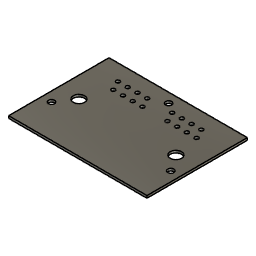
rj45-footprint v1 (Autodesk Fusion 360 design; units mm, degrees)
Autodesk Fusion 360 part; units mm, degrees
sketch "Skizze1" plane through (0, 0, 0) normal (0, 0, 1) x (1, 0, 0)
  circle A0 centre (16.27, 7.5) radius 0.5
  circle A1 centre (18.81, 7.5) radius 0.5
  circle A2 centre (21.35, 7.5) radius 0.5
  circle A3 centre (23.89, 7.5) radius 0.5
  circle A4 centre (17.54, 5) radius 0.5
  circle A5 centre (20.08, 5) radius 0.5
  circle A6 centre (22.62, 5) radius 0.5
  circle A7 centre (25.16, 5) radius 0.5
  circle A8 centre (31.66, 5) radius 0.5
  circle A9 centre (36.74, 5) radius 0.5
  circle A10 centre (35.47, 7.5) radius 0.5
  circle A11 centre (34.2, 5) radius 0.5
  circle A12 centre (39.28, 5) radius 0.5
  circle A13 centre (38.01, 7.5) radius 0.5
  circle A14 centre (32.93, 7.5) radius 0.5
  circle A15 centre (30.39, 7.5) radius 0.5
  circle A16 centre (15.125, -1.55) radius 1.5
  circle A17 centre (40.425, -1.55) radius 1.5
  circle A18 centre (12.225, -5.8) radius 0.8
  circle A19 centre (43.325, -5.8) radius 0.8
  circle A20 centre (27.775, 9.2) radius 0.8
  line L0 (27.775, 9.2) -> (27.775, -15) construction
  line L1 (16.27, 7.5) -> (39.28, 7.5) construction
  line L2 (39.28, 7.5) -> (39.28, 5) construction
  line L3 (39.28, 5) -> (16.27, 5) construction
  line L4 (16.27, 5) -> (16.27, 7.5) construction
  line L5 (12.225, 9.2) -> (43.325, 9.2)
  line L6 (43.325, 9.2) -> (43.325, -12)
  line L7 (43.325, -12) -> (12.225, -12)
  line L8 (12.225, -12) -> (12.225, 9.2)
  line L9 (45.825, -14.5) -> (9.725, -14.5)
  line L10 (9.725, -14.5) -> (9.725, 11.7)
  line L11 (9.725, 11.7) -> (45.825, 11.7)
  line L12 (45.825, 11.7) -> (45.825, -14.5)
  dimension "d1" = 1
  dimension "d2" = 2.54
  dimension "d3" = 2.54
  dimension "d4" = 2.54
  dimension "d5" = 2.54
  dimension "d6" = 2.54
  dimension "d7" = 2.54
  dimension "d9" = 2.5
  dimension "d10" = 1
  dimension "d11" = 2.54
  dimension "d12" = 2.54
  dimension "d13" = 2.54
  dimension "d14" = 2.54
  dimension "d15" = 2.54
  dimension "d16" = 2.54
  dimension "d18" = 2.5
  dimension "d19" = 6.5
  dimension "d20" = 1.6
  dimension "d21" = 3
  dimension "d22" = 31.1
  dimension "d23" = 25.3
  dimension "d24" = 2.9
  dimension "d25" = 1.27
  dimension "d26" = 1.27
  dimension "d27" = 15
  dimension "d29" = 4.25
  dimension "d30" = 6.55
  dimension "d31" = 21.2
  dimension "d32" = -2.5
  constraint equal A0 A1
  constraint equal A1 A2
  constraint equal A2 A3
  constraint equal A4 A5
  constraint equal A0 A4
  constraint equal A5 A6
  constraint equal A6 A7
  constraint horizontal A0.centre A1.centre
  constraint horizontal A1.centre A2.centre
  constraint horizontal A2.centre A3.centre
  constraint horizontal A4.centre A5.centre
  constraint horizontal A5.centre A6.centre
  constraint horizontal A6.centre A7.centre
  constraint equal A14 A15
  constraint equal A10 A14
  constraint equal A10 A13
  constraint equal A8 A11
  constraint equal A8 A15
  constraint equal A9 A11
  constraint equal A9 A12
  constraint horizontal A14.centre A15.centre
  constraint horizontal A14.centre A10.centre
  constraint horizontal A13.centre A10.centre
  constraint horizontal A8.centre A11.centre
  constraint horizontal A11.centre A9.centre
  constraint horizontal A9.centre A12.centre
  constraint horizontal A3.centre A15.centre
  constraint equal A18 A19
  constraint horizontal A18.centre A19.centre
  constraint horizontal A16.centre A17.centre
  constraint equal A16 A17
  constraint equal A18 A20
  constraint coincident A20.centre L0.start
  constraint vertical L0
  constraint symmetric A16.centre A17.centre L0
  constraint symmetric A18.centre A19.centre L0
  constraint horizontal L1
  constraint vertical L2
  constraint horizontal L3
  constraint vertical L4
  constraint coincident A12.centre L2.end
  constraint coincident A0.centre L1.start
  constraint symmetric L0 L2 L4
  constraint horizontal L5
  constraint vertical L6
  constraint horizontal L7
  constraint vertical L8
  constraint coincident A20.centre L5
  constraint coincident A18.centre L8
  constraint coincident A19.centre L6
  measures "d1" diameter of A0
  measures "d2" horizontal distance of A0.centre A1.centre
  measures "d3" horizontal distance of A1.centre A2.centre
  measures "d4" horizontal distance of A2.centre A3.centre
  measures "d5" distance of A4.centre A5.centre
  measures "d6" distance of A5.centre A6.centre
  measures "d7" distance of A6.centre A7.centre
  measures "d9" vertical distance of A0.centre A4.centre
  measures "d10" diameter of A15
  measures "d11" horizontal distance of A14.centre A15.centre
  measures "d12" horizontal distance of A14.centre A10.centre
  measures "d13" horizontal distance of A13.centre A10.centre
  measures "d14" distance of A8.centre A11.centre
  measures "d15" distance of A11.centre A9.centre
  measures "d16" distance of A9.centre A12.centre
  measures "d18" vertical distance of A15.centre A8.centre
  measures "d19" distance of A3.centre A15.centre
  measures "d20" diameter of A18
  measures "d21" diameter of A16
  measures "d22" distance of A18.centre A19.centre
  measures "d23" distance of A16.centre A17.centre
  measures "d24" horizontal distance of A17.centre A19.centre
  measures "d25" horizontal distance of A0.centre A4.centre
  measures "d26" horizontal distance of A15.centre A8.centre
  measures "d27" vertical distance of A18.centre A20.centre
  measures "d29" vertical distance of A16.centre A18.centre
  measures "d30" vertical distance of A4.centre A16.centre
  measures "d31" distance of L5 L7
extrude "Extrusion1" add sketch "Skizze1" along normal blind 0.6 contours A18 A19 A20 L5 L6 L7 L8 | L9 L10 L11 L12
